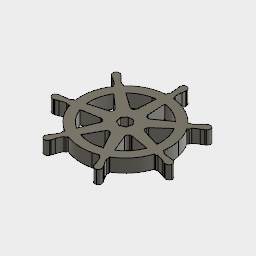
k8s-logo (Autodesk Fusion 360 design; units mm, degrees)
Autodesk Fusion 360 part; units mm, degrees
sketch "Sketch1" plane through (0, 0, 0) normal (0, 1, 0) x (1, 0, 0)
  spline S0 degree 3 poles (-0.04, 69.9579) (-2.177, 69.9577) (-3.9098, 68.0329) (-3.9095, 65.6585) knots 0 0 0 0 1 1 1 1
  spline S1 degree 3 poles (-3.9095, 65.6585) (-3.9095, 65.622) (-3.9021, 65.5872) (-3.9013, 65.551) knots 0 0 0 0 1 1 1 1
  spline S2 degree 3 poles (-3.9013, 65.551) (-3.9044, 65.2284) (-3.92, 64.8397) (-3.9095, 64.5588) knots 0 0 0 0 1 1 1 1
  spline S3 degree 3 poles (-3.9095, 64.5588) (-3.8586, 63.1893) (-3.5601, 62.1412) (-3.3804, 60.8794) knots 0 0 0 0 1 1 1 1
  spline S4 degree 3 poles (-3.3804, 60.8794) (-3.0549, 58.1789) (-2.7821, 55.9404) (-2.9504, 53.8597) knots 0 0 0 0 1 1 1 1
  spline S5 degree 3 poles (-2.9504, 53.8597) (-3.1141, 53.0751) (-3.692, 52.3576) (-4.2072, 51.8588) knots 0 0 0 0 1 1 1 1
  line L0 (-4.2072, 51.8588) -> (-4.2981, 50.2217)
  spline S6 degree 3 poles (-4.2981, 50.2217) (-6.6204, 50.0293) (-8.9581, 49.677) (-11.2931, 49.1468) knots 0 0 0 0 1 1 1 1
  spline S7 degree 3 poles (-11.2931, 49.1468) (-21.3405, 46.8655) (-29.9912, 41.69) (-36.5773, 34.7022) knots 0 0 0 0 1 1 1 1
  spline S8 degree 3 poles (-36.5773, 34.7022) (-37.0047, 34.9938) (-37.7523, 35.5301) (-37.9747, 35.6944) knots 0 0 0 0 1 1 1 1
  spline S9 degree 3 poles (-37.9747, 35.6944) (-38.6655, 35.6011) (-39.3638, 35.3879) (-40.2732, 35.9176) knots 0 0 0 0 1 1 1 1
  spline S10 degree 3 poles (-40.2732, 35.9176) (-42.0049, 37.0833) (-43.5821, 38.6923) (-45.4905, 40.6305) knots 0 0 0 0 1 1 1 1
  spline S11 degree 3 poles (-45.4905, 40.6305) (-46.3649, 41.5577) (-46.9982, 42.4406) (-48.0371, 43.3342) knots 0 0 0 0 1 1 1 1
  spline S12 degree 3 poles (-48.0371, 43.3342) (-48.273, 43.5372) (-48.6331, 43.8117) (-48.897, 44.0205) knots 0 0 0 0 1 1 1 1
  spline S13 degree 3 poles (-48.897, 44.0205) (-49.7092, 44.6681) (-50.6672, 45.0058) (-51.5924, 45.0375) knots 0 0 0 0 1 1 1 1
  spline S14 degree 3 poles (-51.5924, 45.0375) (-52.782, 45.0782) (-53.9271, 44.6132) (-54.6765, 43.6732) knots 0 0 0 0 1 1 1 1
  spline S15 degree 3 poles (-54.6765, 43.6732) (-56.0087, 42.0023) (-55.5822, 39.4484) (-53.7256, 37.9682) knots 0 0 0 0 1 1 1 1
  spline S16 degree 3 poles (-53.7256, 37.9682) (-53.7068, 37.9532) (-53.6867, 37.9415) (-53.6678, 37.9268) knots 0 0 0 0 1 1 1 1
  spline S17 degree 3 poles (-53.6678, 37.9268) (-53.4126, 37.72) (-53.1002, 37.455) (-52.8657, 37.2819) knots 0 0 0 0 1 1 1 1
  spline S18 degree 3 poles (-52.8657, 37.2819) (-51.7633, 36.4679) (-50.7562, 36.0512) (-49.6577, 35.405) knots 0 0 0 0 1 1 1 1
  spline S19 degree 3 poles (-49.6577, 35.405) (-47.3434, 33.9758) (-45.4248, 32.7907) (-43.903, 31.3619) knots 0 0 0 0 1 1 1 1
  spline S20 degree 3 poles (-43.903, 31.3619) (-43.3087, 30.7284) (-43.2049, 29.6122) (-43.1258, 29.1294) knots 0 0 0 0 1 1 1 1
  line L1 (-43.1258, 29.1294) -> (-41.8855, 28.0215)
  spline S21 degree 3 poles (-41.8855, 28.0215) (-48.5248, 18.0298) (-51.5976, 5.6881) (-49.7817, -6.887) knots 0 0 0 0 1 1 1 1
  line L2 (-49.7817, -6.887) -> (-51.4023, -7.3583)
  spline S22 degree 3 poles (-51.4023, -7.3583) (-51.8294, -7.9098) (-52.4329, -8.7777) (-53.0642, -9.0367) knots 0 0 0 0 1 1 1 1
  spline S23 degree 3 poles (-53.0642, -9.0367) (-55.0552, -9.6638) (-57.296, -9.8941) (-60.0012, -10.1777) knots 0 0 0 0 1 1 1 1
  spline S24 degree 3 poles (-60.0012, -10.1777) (-61.2713, -10.2833) (-62.3672, -10.2203) (-63.7137, -10.4754) knots 0 0 0 0 1 1 1 1
  spline S25 degree 3 poles (-63.7137, -10.4754) (-64.01, -10.5315) (-64.4229, -10.6391) (-64.7472, -10.7152) knots 0 0 0 0 1 1 1 1
  spline S26 degree 3 poles (-64.7472, -10.7152) (-64.7585, -10.7175) (-64.769, -10.7209) (-64.7803, -10.7234) knots 0 0 0 0 1 1 1 1
  spline S27 degree 3 poles (-64.7803, -10.7234) (-64.7979, -10.7275) (-64.8212, -10.7361) (-64.8381, -10.74) knots 0 0 0 0 1 1 1 1
  spline S28 degree 3 poles (-64.8381, -10.74) (-67.1189, -11.291) (-68.584, -13.3874) (-68.1124, -15.4528) knots 0 0 0 0 1 1 1 1
  spline S29 degree 3 poles (-68.1124, -15.4528) (-67.6406, -17.5188) (-65.4128, -18.7752) (-63.1183, -18.2806) knots 0 0 0 0 1 1 1 1
  spline S30 degree 3 poles (-63.1183, -18.2806) (-63.1018, -18.2768) (-63.0777, -18.2762) (-63.0605, -18.2723) knots 0 0 0 0 1 1 1 1
  spline S31 degree 3 poles (-63.0605, -18.2723) (-63.0346, -18.2664) (-63.0118, -18.2538) (-62.9861, -18.2475) knots 0 0 0 0 1 1 1 1
  spline S32 degree 3 poles (-62.9861, -18.2475) (-62.6662, -18.1773) (-62.2654, -18.0992) (-61.9856, -18.0243) knots 0 0 0 0 1 1 1 1
  spline S33 degree 3 poles (-61.9856, -18.0243) (-60.6618, -17.6699) (-59.7031, -17.1491) (-58.5129, -16.6931) knots 0 0 0 0 1 1 1 1
  spline S34 degree 3 poles (-58.5129, -16.6931) (-55.9526, -15.7748) (-53.832, -15.0077) (-51.7661, -14.7087) knots 0 0 0 0 1 1 1 1
  spline S35 degree 3 poles (-51.7661, -14.7087) (-50.9032, -14.6412) (-49.9941, -15.2411) (-49.5419, -15.4942) knots 0 0 0 0 1 1 1 1
  line L3 (-49.5419, -15.4942) -> (-47.8552, -15.2048)
  spline S36 degree 3 poles (-47.8552, -15.2048) (-43.9737, -27.2388) (-35.8394, -36.9655) (-25.5392, -43.0688) knots 0 0 0 0 1 1 1 1
  line L4 (-25.5392, -43.0688) -> (-26.242, -44.7555)
  spline S37 degree 3 poles (-26.242, -44.7555) (-25.9887, -45.4104) (-25.7093, -46.2966) (-25.898, -46.9434) knots 0 0 0 0 1 1 1 1
  spline S38 degree 3 poles (-25.898, -46.9434) (-26.6491, -48.8911) (-27.9356, -50.9468) (-29.4005, -53.2387) knots 0 0 0 0 1 1 1 1
  spline S39 degree 3 poles (-29.4005, -53.2387) (-30.1098, -54.2975) (-30.8357, -55.1192) (-31.4758, -56.331) knots 0 0 0 0 1 1 1 1
  spline S40 degree 3 poles (-31.4758, -56.331) (-31.629, -56.621) (-31.8241, -57.0664) (-31.9719, -57.3728) knots 0 0 0 0 1 1 1 1
  spline S41 degree 3 poles (-31.9719, -57.3728) (-32.9664, -59.5007) (-32.2369, -61.9515) (-30.3265, -62.8712) knots 0 0 0 0 1 1 1 1
  spline S42 degree 3 poles (-30.3265, -62.8712) (-28.4041, -63.7966) (-26.0179, -62.8205) (-24.9853, -60.6884) knots 0 0 0 0 1 1 1 1
  spline S43 degree 3 poles (-24.9853, -60.6884) (-24.9837, -60.6853) (-24.9785, -60.6831) (-24.977, -60.6801) knots 0 0 0 0 1 1 1 1
  spline S44 degree 3 poles (-24.977, -60.6801) (-24.976, -60.6777) (-24.9781, -60.6741) (-24.977, -60.6719) knots 0 0 0 0 1 1 1 1
  spline S45 degree 3 poles (-24.977, -60.6719) (-24.8299, -60.3695) (-24.6215, -59.9722) (-24.4975, -59.6879) knots 0 0 0 0 1 1 1 1
  spline S46 degree 3 poles (-24.4975, -59.6879) (-23.9492, -58.432) (-23.7668, -57.3556) (-23.3812, -56.1409) knots 0 0 0 0 1 1 1 1
  spline S47 degree 3 poles (-23.3812, -56.1409) (-22.3574, -53.5691) (-21.7949, -50.8706) (-20.3855, -49.1892) knots 0 0 0 0 1 1 1 1
  spline S48 degree 3 poles (-20.3855, -49.1892) (-19.9995, -48.7287) (-19.3703, -48.5517) (-18.718, -48.377) knots 0 0 0 0 1 1 1 1
  line L5 (-18.718, -48.377) -> (-17.8415, -46.7895)
  spline S49 degree 3 poles (-17.8415, -46.7895) (-8.862, -50.2362) (1.1891, -51.1611) (11.2296, -48.8814) knots 0 0 0 0 1 1 1 1
  spline S50 degree 3 poles (11.2296, -48.8814) (13.5201, -48.3613) (15.7313, -47.6882) (17.8689, -46.8804) knots 0 0 0 0 1 1 1 1
  spline S51 degree 3 poles (17.8689, -46.8804) (18.1153, -47.3174) (18.573, -48.1572) (18.6958, -48.3687) knots 0 0 0 0 1 1 1 1
  spline S52 degree 3 poles (18.6958, -48.3687) (19.3587, -48.5844) (20.0823, -48.6958) (20.6719, -49.5676) knots 0 0 0 0 1 1 1 1
  spline S53 degree 3 poles (20.6719, -49.5676) (21.7263, -51.3692) (22.4475, -53.5004) (23.326, -56.0747) knots 0 0 0 0 1 1 1 1
  spline S54 degree 3 poles (23.326, -56.0747) (23.7116, -57.2895) (23.9021, -58.3658) (24.4505, -59.6218) knots 0 0 0 0 1 1 1 1
  spline S55 degree 3 poles (24.4505, -59.6218) (24.5754, -59.9081) (24.7828, -60.311) (24.93, -60.614) knots 0 0 0 0 1 1 1 1
  spline S56 degree 3 poles (24.93, -60.614) (25.9605, -62.7531) (28.3543, -63.7325) (30.2796, -62.8051) knots 0 0 0 0 1 1 1 1
  spline S57 degree 3 poles (30.2796, -62.8051) (32.1897, -61.8849) (32.92, -59.4343) (31.9249, -57.3067) knots 0 0 0 0 1 1 1 1
  spline S58 degree 3 poles (31.9249, -57.3067) (31.7771, -57.0003) (31.5738, -56.5548) (31.4206, -56.2649) knots 0 0 0 0 1 1 1 1
  spline S59 degree 3 poles (31.4206, -56.2649) (30.7804, -55.0532) (30.0546, -54.2396) (29.3453, -53.1808) knots 0 0 0 0 1 1 1 1
  spline S60 degree 3 poles (29.3453, -53.1808) (27.8802, -50.889) (26.6651, -48.9851) (25.9139, -47.0375) knots 0 0 0 0 1 1 1 1
  spline S61 degree 3 poles (25.9139, -47.0375) (25.5998, -46.033) (25.9669, -45.4083) (26.2116, -44.7555) knots 0 0 0 0 1 1 1 1
  spline S62 degree 3 poles (26.2116, -44.7555) (26.0651, -44.5876) (25.7515, -43.6389) (25.5667, -43.1928) knots 0 0 0 0 1 1 1 1
  spline S63 degree 3 poles (25.5667, -43.1928) (36.271, -36.8724) (44.1665, -26.783) (47.8744, -15.1304) knots 0 0 0 0 1 1 1 1
  spline S64 degree 3 poles (47.8744, -15.1304) (48.375, -15.2091) (49.2453, -15.3631) (49.528, -15.4198) knots 0 0 0 0 1 1 1 1
  spline S65 degree 3 poles (49.528, -15.4198) (50.11, -15.036) (50.645, -14.5352) (51.6943, -14.6178) knots 0 0 0 0 1 1 1 1
  spline S66 degree 3 poles (51.6943, -14.6178) (53.7602, -14.9166) (55.8807, -15.684) (58.4411, -16.6022) knots 0 0 0 0 1 1 1 1
  spline S67 degree 3 poles (58.4411, -16.6022) (59.6313, -17.0581) (60.59, -17.5873) (61.9138, -17.9416) knots 0 0 0 0 1 1 1 1
  spline S68 degree 3 poles (61.9138, -17.9416) (62.1936, -18.0165) (62.5944, -18.0864) (62.9143, -18.1566) knots 0 0 0 0 1 1 1 1
  spline S69 degree 3 poles (62.9143, -18.1566) (62.94, -18.1629) (62.9628, -18.1755) (62.9887, -18.1814) knots 0 0 0 0 1 1 1 1
  spline S70 degree 3 poles (62.9887, -18.1814) (63.006, -18.1853) (63.03, -18.1859) (63.0466, -18.1897) knots 0 0 0 0 1 1 1 1
  spline S71 degree 3 poles (63.0466, -18.1897) (65.3411, -18.6836) (67.5693, -17.428) (68.0406, -15.3619) knots 0 0 0 0 1 1 1 1
  spline S72 degree 3 poles (68.0406, -15.3619) (68.5117, -13.2963) (67.0472, -11.1995) (64.7663, -10.649) knots 0 0 0 0 1 1 1 1
  spline S73 degree 3 poles (64.7663, -10.649) (64.4346, -10.5736) (63.9641, -10.4455) (63.6419, -10.3845) knots 0 0 0 0 1 1 1 1
  spline S74 degree 3 poles (63.6419, -10.3845) (62.2954, -10.1294) (61.1995, -10.1923) (59.9294, -10.0868) knots 0 0 0 0 1 1 1 1
  spline S75 degree 3 poles (59.9294, -10.0868) (57.2242, -9.8033) (54.9834, -9.5728) (52.9924, -8.9458) knots 0 0 0 0 1 1 1 1
  spline S76 degree 3 poles (52.9924, -8.9458) (52.1806, -8.6308) (51.603, -7.6649) (51.3222, -7.2673) knots 0 0 0 0 1 1 1 1
  line L6 (51.3222, -7.2673) -> (49.7595, -6.8126)
  spline S77 degree 3 poles (49.7595, -6.8126) (50.5697, -0.9509) (50.3513, 5.1496) (48.9492, 11.2535) knots 0 0 0 0 1 1 1 1
  spline S78 degree 3 poles (48.9492, 11.2535) (47.5341, 17.4142) (45.0333, 23.0489) (41.698, 28.0132) knots 0 0 0 0 1 1 1 1
  spline S79 degree 3 poles (41.698, 28.0132) (42.0988, 28.3776) (42.8558, 29.048) (43.0705, 29.2452) knots 0 0 0 0 1 1 1 1
  spline S80 degree 3 poles (43.0705, 29.2452) (43.1332, 29.9395) (43.0793, 30.6674) (43.7981, 31.4363) knots 0 0 0 0 1 1 1 1
  spline S81 degree 3 poles (43.7981, 31.4363) (45.3198, 32.8652) (47.2386, 34.0501) (49.5528, 35.4794) knots 0 0 0 0 1 1 1 1
  spline S82 degree 3 poles (49.5528, 35.4794) (50.6513, 36.1257) (51.6667, 36.5422) (52.7691, 37.3563) knots 0 0 0 0 1 1 1 1
  spline S83 degree 3 poles (52.7691, 37.3563) (53.0184, 37.5404) (53.3589, 37.8319) (53.6208, 38.0426) knots 0 0 0 0 1 1 1 1
  spline S84 degree 3 poles (53.6208, 38.0426) (55.4769, 39.5233) (55.9043, 42.077) (54.5716, 43.7476) knots 0 0 0 0 1 1 1 1
  spline S85 degree 3 poles (54.5716, 43.7476) (53.2389, 45.4182) (50.6565, 45.5756) (48.8004, 44.0949) knots 0 0 0 0 1 1 1 1
  spline S86 degree 3 poles (48.8004, 44.0949) (48.5362, 43.8857) (48.1777, 43.6127) (47.9405, 43.4086) knots 0 0 0 0 1 1 1 1
  spline S87 degree 3 poles (47.9405, 43.4086) (46.9016, 42.5149) (46.26, 41.6321) (45.3856, 40.7049) knots 0 0 0 0 1 1 1 1
  spline S88 degree 3 poles (45.3856, 40.7049) (43.4773, 38.7666) (41.9, 37.1495) (40.1683, 35.9838) knots 0 0 0 0 1 1 1 1
  spline S89 degree 3 poles (40.1683, 35.9838) (39.418, 35.5469) (38.3189, 35.6981) (37.8202, 35.7275) knots 0 0 0 0 1 1 1 1
  line L7 (37.8202, 35.7275) -> (36.3484, 34.6774)
  spline S90 degree 3 poles (36.3484, 34.6774) (27.9561, 43.4776) (16.5299, 49.1039) (4.2264, 50.1969) knots 0 0 0 0 1 1 1 1
  spline S91 degree 3 poles (4.2264, 50.1969) (4.192, 50.7125) (4.1469, 51.6445) (4.1354, 51.9249) knots 0 0 0 0 1 1 1 1
  spline S92 degree 3 poles (4.1354, 51.9249) (3.6317, 52.4069) (3.0233, 52.8184) (2.8704, 53.8597) knots 0 0 0 0 1 1 1 1
  spline S93 degree 3 poles (2.8704, 53.8597) (2.7021, 55.9404) (2.9831, 58.1789) (3.3086, 60.8794) knots 0 0 0 0 1 1 1 1
  spline S94 degree 3 poles (3.3086, 60.8794) (3.4883, 62.1412) (3.7868, 63.1893) (3.8378, 64.5588) knots 0 0 0 0 1 1 1 1
  spline S95 degree 3 poles (3.8378, 64.5588) (3.8494, 64.8701) (3.8308, 65.3219) (3.8295, 65.6585) knots 0 0 0 0 1 1 1 1
  spline S96 degree 3 poles (3.8295, 65.6585) (3.8293, 68.0329) (2.097, 69.9582) (-0.04, 69.9579) knots 0 0 0 0 1 1 1 1
  line L8 (-4.8852, 39.9443) -> (-6.0345, 19.6458)
  line L9 (-6.0345, 19.6458) -> (-6.1172, 19.6044)
  spline S97 degree 3 poles (-6.1172, 19.6044) (-6.1942, 17.7885) (-7.6888, 16.3385) (-9.5237, 16.3385) knots 0 0 0 0 1 1 1 1
  spline S98 degree 3 poles (-9.5237, 16.3385) (-10.2753, 16.3385) (-10.9691, 16.5799) (-11.5328, 16.9917) knots 0 0 0 0 1 1 1 1
  line L10 (-11.5328, 16.9917) -> (-11.5659, 16.9751)
  line L11 (-11.5659, 16.9751) -> (-28.2099, 28.7739)
  spline S99 degree 3 poles (-28.2099, 28.7739) (-23.0945, 33.8039) (-16.5516, 37.5211) (-9.011, 39.2332) knots 0 0 0 0 1 1 1 1
  spline S100 degree 3 poles (-9.011, 39.2332) (-7.6336, 39.546) (-6.2568, 39.778) (-4.8852, 39.9443) knots 0 0 0 0 1 1 1 1
  spline S101 degree 3 poles (4.8134, 39.9443) (13.617, 38.8615) (21.7587, 34.8752) (27.9976, 28.7656) knots 0 0 0 0 1 1 1 1
  line L12 (27.9976, 28.7656) -> (11.4611, 17.0413)
  line L13 (11.4611, 17.0413) -> (11.4032, 17.0661)
  spline S102 degree 3 poles (11.4032, 17.0661) (9.9355, 15.9941) (7.8675, 16.26) (6.7234, 17.6945) knots 0 0 0 0 1 1 1 1
  spline S103 degree 3 poles (6.7234, 17.6945) (6.2547, 18.2821) (6.0088, 18.973) (5.9793, 19.6706) knots 0 0 0 0 1 1 1 1
  line L14 (5.9793, 19.6706) -> (5.9627, 19.6788)
  line L15 (5.9627, 19.6788) -> (4.8134, 39.9443)
  line L16 (-34.2457, 21.1919) -> (-19.0487, 7.599)
  line L17 (-19.0487, 7.599) -> (-19.0652, 7.5163)
  spline S104 degree 3 poles (-19.0652, 7.5163) (-17.6935, 6.3238) (-17.4912, 4.2545) (-18.6353, 2.8199) knots 0 0 0 0 1 1 1 1
  spline S105 degree 3 poles (-18.6353, 2.8199) (-19.1039, 2.2323) (-19.7312, 1.8381) (-20.4047, 1.6541) knots 0 0 0 0 1 1 1 1
  line L18 (-20.4047, 1.6541) -> (-20.4212, 1.588)
  line L19 (-20.4212, 1.588) -> (-39.9011, -4.0344)
  spline S106 degree 3 poles (-39.9011, -4.0344) (-40.8926, 5.0316) (-38.7559, 13.8444) (-34.2457, 21.1919) knots 0 0 0 0 1 1 1 1
  spline S107 degree 3 poles (34.0582, 21.1837) (36.3161, 17.5238) (38.026, 13.4361) (39.0439, 9.0046) knots 0 0 0 0 1 1 1 1
  spline S108 degree 3 poles (39.0439, 9.0046) (40.0496, 4.6262) (40.302, 0.2556) (39.8873, -3.9683) knots 0 0 0 0 1 1 1 1
  line L20 (39.8873, -3.9683) -> (20.3081, 1.6707)
  line L21 (20.3081, 1.6707) -> (20.2916, 1.7533)
  spline S109 degree 3 poles (20.2916, 1.7533) (18.5383, 2.2325) (17.4608, 4.016) (17.869, 5.8048) knots 0 0 0 0 1 1 1 1
  spline S110 degree 3 poles (17.869, 5.8048) (18.0362, 6.5376) (18.4252, 7.1575) (18.9521, 7.6155) knots 0 0 0 0 1 1 1 1
  line L22 (18.9521, 7.6155) -> (18.9439, 7.6569)
  line L23 (18.9439, 7.6569) -> (34.0582, 21.1837)
  line L24 (-3.1571, 6.5489) -> (3.0688, 6.5489)
  line L25 (3.0688, 6.5489) -> (6.9384, 1.712)
  line L26 (6.9384, 1.712) -> (5.5493, -4.3238)
  line L27 (5.5493, -4.3238) -> (-0.04, -7.011)
  line L28 (-0.04, -7.011) -> (-5.6459, -4.3155)
  line L29 (-5.6459, -4.3155) -> (-7.0349, 1.7203)
  line L30 (-7.0349, 1.7203) -> (-3.1571, 6.5489)
  spline S111 degree 3 poles (16.8024, -10.0041) (17.0669, -9.9907) (17.3304, -10.0146) (17.5879, -10.062) knots 0 0 0 0 1 1 1 1
  line L31 (17.5879, -10.062) -> (17.6209, -10.0206)
  line L32 (17.6209, -10.0206) -> (37.7706, -13.4271)
  spline S112 degree 3 poles (37.7706, -13.4271) (34.8217, -21.7121) (29.1788, -28.8894) (21.6393, -33.6926) knots 0 0 0 0 1 1 1 1
  line L33 (21.6393, -33.6926) -> (13.8175, -14.7997)
  line L34 (13.8175, -14.7997) -> (13.8423, -14.7666)
  spline S113 degree 3 poles (13.8423, -14.7666) (13.1238, -13.0971) (13.8429, -11.1393) (15.496, -10.3431) knots 0 0 0 0 1 1 1 1
  spline S114 degree 3 poles (15.496, -10.3431) (15.9192, -10.1392) (16.3614, -10.0264) (16.8024, -10.0041) knots 0 0 0 0 1 1 1 1
  spline S115 degree 3 poles (-17.0395, -10.0868) (-15.5018, -10.1083) (-14.1226, -11.1756) (-13.7653, -12.7409) knots 0 0 0 0 1 1 1 1
  spline S116 degree 3 poles (-13.7653, -12.7409) (-13.598, -13.4737) (-13.6794, -14.1997) (-13.9554, -14.841) knots 0 0 0 0 1 1 1 1
  line L35 (-13.9554, -14.841) -> (-13.8976, -14.9154)
  line L36 (-13.8976, -14.9154) -> (-21.6366, -33.6181)
  spline S117 degree 3 poles (-21.6366, -33.6181) (-28.8722, -28.9751) (-34.6354, -22.023) (-37.7183, -13.4933) knots 0 0 0 0 1 1 1 1
  line L37 (-37.7183, -13.4933) -> (-17.7423, -10.1033)
  line L38 (-17.7423, -10.1033) -> (-17.7092, -10.1447)
  spline S118 degree 3 poles (-17.7092, -10.1447) (-17.4858, -10.1035) (-17.2592, -10.0837) (-17.0395, -10.0868) knots 0 0 0 0 1 1 1 1
  spline S119 degree 3 poles (-0.164, -18.2806) (0.3716, -18.2609) (0.9151, -18.3708) (1.4317, -18.6196) knots 0 0 0 0 1 1 1 1
  spline S120 degree 3 poles (1.4317, -18.6196) (2.1089, -18.9457) (2.6321, -19.4592) (2.9614, -20.0748) knots 0 0 0 0 1 1 1 1
  line L39 (2.9614, -20.0748) -> (3.0358, -20.0748)
  line L40 (3.0358, -20.0748) -> (12.8832, -37.868)
  spline S121 degree 3 poles (12.8832, -37.868) (11.6052, -38.2964) (10.2914, -38.6626) (8.9476, -38.9677) knots 0 0 0 0 1 1 1 1
  spline S122 degree 3 poles (8.9476, -38.9677) (1.4163, -40.6777) (-6.091, -40.1596) (-12.8888, -37.8432) knots 0 0 0 0 1 1 1 1
  line L41 (-12.8888, -37.8432) -> (-3.0662, -20.0831)
  line L42 (-3.0662, -20.0831) -> (-3.0496, -20.0831)
  spline S123 degree 3 poles (-3.0496, -20.0831) (-2.4602, -18.9812) (-1.3424, -18.3239) (-0.164, -18.2806) knots 0 0 0 0 1 1 1 1
  point P0 (12.309, 81.3256)
  point P1 (-52.3417, 50.4349)
  point P2 (-68.2915, -18.9538)
  point P3 (-68.2666, -18.9921)
  point P4 (-23.5514, -74.5884)
  point P5 (48.2201, -74.5719)
  point P6 (92.9447, -18.9348)
  point P7 (76.9706, 50.4514)
  point P8 (12.3114, 81.3258)
extrude "Extrude1" add sketch "Sketch1" along normal blind 15
